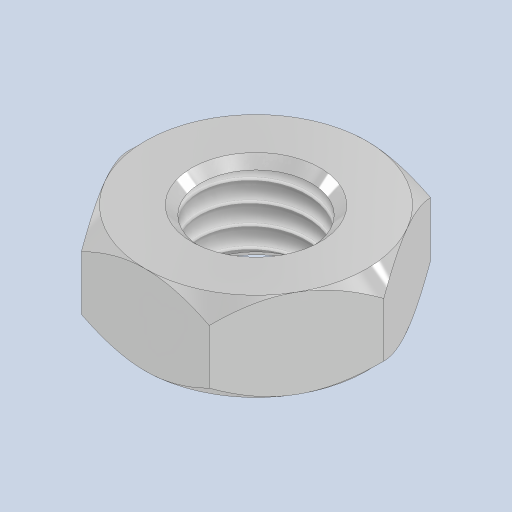
# Autodesk Inventor part: Porca 2,5mm
Saved by Autodesk Inventor 2024.3 (Build 283343000, 343)
## iProperties
Created: 2025-02-16
Part Number: Porca 2,5mm
Material: Aço
Document SubType Name: Modeling
Designer: Cliente
Density: 7.85 g/cm^3
Appearance: Alumínio - Polido
Author: Cliente
Autodesk Inventor part; units mm, degrees
ref_plane "YZ Plane" through (0, 0, 0) normal (1, 0, 0) x (0, 1, 0)
ref_plane "XZ Plane" through (0, 0, 0) normal (0, 1, 0) x (-1, 0, 0)
ref_plane "XY Plane" through (0, 0, 0) normal (0, 0, 1) x (1, 0, 0)
sketch "Esboço1" plane through (0, 0, 0) normal (0, 1, 0) x (-1, 0, 0)
  line L0 (2.8868, 0) -> (1.4434, -2.5)
  line L1 (1.4434, -2.5) -> (-1.4434, -2.5)
  line L2 (-1.4434, -2.5) -> (-2.8868, 0)
  line L3 (-2.8868, 0) -> (-1.4434, 2.5)
  line L4 (-1.4434, 2.5) -> (1.4434, 2.5)
  line L5 (1.4434, 2.5) -> (2.8868, 0)
  circle A0 centre (0, 0) radius 1.25
  dimension "d1" = 5
  dimension "d3" = 2.5
  constraints: 12 end point, 2 coincident, 1 centre point, 1 horizontal alignment, 13 other
  measures "d1" distance between parallel lines of L4 L1
  measures "d3" diameter of A0
extrude "Extrusão1" add sketch "Esboço1" along normal blind 2
thread "Rosca1" size "M2.5x0.45" class "6H" standard "ANSI Metric M Profile" length 20
chamfer "Chanfro1" distance 0.2 angle 45 2 edges at (1.25, 2, 0) (1.25, 0, 0)
sketch "Esboço2" plane through (0, 0, 0) normal (1, 0, 0) x (0, 1, 0)
  line L0 (0, -2.5) -> (0, 0) projected
  line L1 (2, -2.5) -> (2, 0) projected
  line L2 (0, 0) -> (2, 0)
  line L3 (2, 0) -> (2, 2.5)
  line L4 (2, 2.5) -> (2, 2.8868)
  line L5 (2, 2.8868) -> (1.6132, 2.8868)
  line L6 (1.6132, 2.8868) -> (2, 2.5)
  line L7 (1, 0) -> (1, 2.8868)
  line L8 (0, 2.5) -> (0, 2.8868)
  line L9 (0, 2.8868) -> (0.3868, 2.8868)
  line L10 (0.3868, 2.8868) -> (0, 2.5)
  dimension "d11" = 2.5
  dimension "d12" = 0.3867
  dimension "d13" = 0.3867
  constraints: 18 end point, 3 perpendicular, 3 symmetric about line, 1 midpoint, 1 point on line, 1 vertical
  measures "d11" distance of L1.end L3.end
  measures "d12" distance of L3.end L4.end
  measures "d13" distance of L4.end L5.end
revolve "Revolução1" cut sketch "Esboço2" angle 360 about axis through (0, 0, 0) along (0, 1, 0)
equation "\"d13\" = d12"
